Autodesk Fusion 360 part; units mm, degrees
(part 4 of 6)
component "611205 AIR - SOFFIT TOP RAIL - DOOR SIDE" placed x (1, 0, 0) y (0, 1, 0) z (0, 0, 1) at (0, 0, 0) in component "610201 AIR - SOFFIT"
component "611209 AIR - SOFFIT TOP RAIL - ROOM SIDE" placed x (1, 0, 0) y (0, 1, 0) z (0, 0, 1) at (0, 0, 0) in component "610201 AIR - SOFFIT"
component "611210 AIR - SOFFIT DOOR-SIDE PLATE" placed x (1, 0, 0) y (0, 1, 0) z (0, 0, 1) at (0, 0, 0) in component "610201 AIR - SOFFIT"
component "611206 AIR - SOFFIT END PLATE - LEFT" placed x (1, 0, 0) y (0, 1, 0) z (0, 0, 1) at (0, 0, 0) in component "610201 AIR - SOFFIT"
component "611203 AIR - SOFFIT FILL" placed x (1, 0, 0) y (0, 1, 0) z (0, 0, 1) at (0, 0, 0) in component "610201 AIR - SOFFIT"
component "611211 AIR - SOFFIT FILL - FRONT" placed x (1, 0, 0) y (0, 1, 0) z (0, 0, 1) at (0, 0, 0) in component "610201 AIR - SOFFIT"
component "611204 AIR - EXHAUST GRILLE" placed x (1, 0, 0) y (0, 1, 0) z (0, 0, 1) at (0, 0, 0) in component "610201 AIR - SOFFIT"
component "838001 HARDWARE - SOCKET HEAD BOLT - M6 X 16 - ISO 4762 8.8 ZINC" placed x (1, 0, 0) y (0, 1, 0) z (0, 0, 1) at (-588, -640, 2340.24) in component "610201 AIR - SOFFIT"
component "838001 HARDWARE - SOCKET HEAD BOLT - M6 X 16 - ISO 4762 8.8 ZINC" placed x (1, 0, 0) y (0, 1, 0) z (0, 0, 1) at (-588, -296, 2340.24) in component "610201 AIR - SOFFIT"
component "838001 HARDWARE - SOCKET HEAD BOLT - M6 X 16 - ISO 4762 8.8 ZINC" placed x (1, 0, 0) y (0, 1, 0) z (0, 0, 1) at (578, -640, 2340.24) in component "610201 AIR - SOFFIT"
component "838001 HARDWARE - SOCKET HEAD BOLT - M6 X 16 - ISO 4762 8.8 ZINC" placed x (1, 0, 0) y (0, 1, 0) z (0, 0, 1) at (578, -296, 2340.24) in component "610201 AIR - SOFFIT"
component "618105 AIR - SOFFIT UNDERSIDE HINGE - HOLD" placed x (1, 0, 0) y (0, 1, 0) z (0, 0, 1) at (-901, -641.14, 2132) in component "610201 AIR - SOFFIT"
component "618105 AIR - SOFFIT UNDERSIDE HINGE - HOLD" placed x (1, 0, 0) y (0, 1, 0) z (0, 0, 1) at (-321, -641.14, 2132) in component "610201 AIR - SOFFIT"
component "618105 AIR - SOFFIT UNDERSIDE HINGE - HOLD" placed x (1, 0, 0) y (0, 1, 0) z (0, 0, 1) at (207.75, -641.14, 2132) in component "610201 AIR - SOFFIT"
component "618105 AIR - SOFFIT UNDERSIDE HINGE - HOLD" placed x (1, 0, 0) y (0, 1, 0) z (0, 0, 1) at (681.25, -641.14, 2132) in component "610201 AIR - SOFFIT"
component "618106 AIR - SOFFIT UNDERSIDE LATCH - HOLD" placed x (1, 0, 0) y (0, 1, 0) z (0, 0, 1) at (-886, -305, 2132) in component "610201 AIR - SOFFIT"
component "618106 AIR - SOFFIT UNDERSIDE LATCH - HOLD" placed x (1, 0, 0) y (0, 1, 0) z (0, 0, 1) at (-306, -305, 2132) in component "610201 AIR - SOFFIT"
component "618106 AIR - SOFFIT UNDERSIDE LATCH - HOLD" placed x (1, 0, 0) y (0, 1, 0) z (0, 0, 1) at (222.75, -305, 2132) in component "610201 AIR - SOFFIT"
component "618106 AIR - SOFFIT UNDERSIDE LATCH - HOLD" placed x (1, 0, 0) y (0, 1, 0) z (0, 0, 1) at (696.25, -305, 2132) in component "610201 AIR - SOFFIT"
component "838002 HARDWARE - SOCKET HEAD BOLT - M6 X 25 - ISO 4762 8.8 ZINC" placed x (1, 0, 0) y (0, 1, 0) z (0, 0, 1) at (-1105, -296, 2340.24) in component "610201 AIR - SOFFIT"
component "838002 HARDWARE - SOCKET HEAD BOLT - M6 X 25 - ISO 4762 8.8 ZINC" placed x (1, 0, 0) y (0, 1, 0) z (0, 0, 1) at (-955, -296, 2340.24) in component "610201 AIR - SOFFIT"
component "610301 AIR - SPLITTER CARTRIDGE - COMMON (EXHAUST)" placed x (1, 0, 0) y (0, 1, 0) z (0, 0, 1) at (0, 0, 0) in component "610201 AIR - SOFFIT"
component "610402 AIR - EXHAUST FAN BOX" placed x (1, 0, 0) y (0, 1, 0) z (0, 0, 1) at (0, 0, 0) in component "610201 AIR - SOFFIT"
component "611301 AIR - CARTRIDGE CASING (1)" placed x (1, 0, 0) y (0, 1, 0) z (0, 0, 1) at (0, 0, 0) in component "610301 AIR - SPLITTER CARTRIDGE - COMMON (EXHAUST)"
component "611302 AIR - CARTRIDGE FILL - LAYER 50 (1)" placed x (1, 0, 0) y (0, 1, 0) z (0, 0, 1) at (-883, -634.14, 2161) in component "610301 AIR - SPLITTER CARTRIDGE - COMMON (EXHAUST)"
component "611302 AIR - CARTRIDGE FILL - LAYER 50 (1)" placed x (1, 0, 0) y (0, 1, 0) z (0, 0, 1) at (-883, -504.14, 2161) in component "610301 AIR - SPLITTER CARTRIDGE - COMMON (EXHAUST)"
component "611302 AIR - CARTRIDGE FILL - LAYER 50 (1)" placed x (1, 0, 0) y (0, 1, 0) z (0, 0, 1) at (-883, -374.14, 2161) in component "610301 AIR - SPLITTER CARTRIDGE - COMMON (EXHAUST)"
component "611401 AIR - FAN BOX CASING - EXHAUST" placed x (1, 0, 0) y (0, 1, 0) z (0, 0, 1) at (0, 0, 0) in component "610402 AIR - EXHAUST FAN BOX"
component "611403 AIR - FAN BOX BULKHEAD - EXHAUST" placed x (1, 0, 0) y (0, 1, 0) z (0, 0, 1) at (0, 0, 0) in component "610402 AIR - EXHAUST FAN BOX"
component "611405 AIR - FAN BOX LINING - EXHAUST SIDE" placed x (1, 0, 0) y (0, 1, 0) z (0, 0, 1) at (867, -633.14, 2162) in component "610402 AIR - EXHAUST FAN BOX"
component "611405 AIR - FAN BOX LINING - EXHAUST SIDE" placed x (1, 0, 0) y (0, 1, 0) z (0, 0, 1) at (867, -375.14, 2162) in component "610402 AIR - EXHAUST FAN BOX"
component "611406 AIR - FAN BOX LINING - EXHAUST FAR END" placed x (1, 0, 0) y (0, 1, 0) z (0, 0, 1) at (0, 0, 0) in component "610402 AIR - EXHAUST FAN BOX"
component "618401 AIR - FAN - NOCTUA NF-A14 INDUSTRIALPPC-3000 PWM" placed x (1, 0, 0) y (0, 1, 0) z (0, 0, 1) at (939.75, -479.14, 2305) in component "610402 AIR - EXHAUST FAN BOX"
component "618401 AIR - FAN - NOCTUA NF-A14 INDUSTRIALPPC-3000 PWM" placed x (1, 0, 0) y (0, 1, 0) z (0, 0, 1) at (1085.25, -479.14, 2305) in component "610402 AIR - EXHAUST FAN BOX"
component "611402 AIR - FAN BOX CASING - SUPPLY" placed x (1, 0, 0) y (0, 1, 0) z (0, 0, 1) at (0, 0, 0) in component "610401 AIR - SUPPLY FAN BOX"
component "611404 AIR - FAN BOX BULKHEAD - SUPPLY" placed x (1, 0, 0) y (0, 1, 0) z (0, 0, 1) at (0, 0, 0) in component "610401 AIR - SUPPLY FAN BOX"
component "611407 AIR - FAN BOX LINING - SUPPLY END" placed x (1, 0, 0) y (0, 1, 0) z (0, 0, 1) at (683, -816, 1795) in component "610401 AIR - SUPPLY FAN BOX"
component "611407 AIR - FAN BOX LINING - SUPPLY END" placed x (1, 0, 0) y (0, 1, 0) z (0, 0, 1) at (927, -816, 1795) in component "610401 AIR - SUPPLY FAN BOX"
component "611408 AIR - FAN BOX LIP ANGLE - SUPPLY" placed x (1, 0, 0) y (0, 1, 0) z (0, 0, 1) at (0, 0, 0) in component "610401 AIR - SUPPLY FAN BOX"
component "618402 AIR - FAN BOX PAD - SUPPLY - RUBBER 40 X 15 X 5 - HOLD" placed x (1, 0, 0) y (0, 1, 0) z (0, 0, 1) at (685, -841.5, 1650) in component "610401 AIR - SUPPLY FAN BOX"
component "618402 AIR - FAN BOX PAD - SUPPLY - RUBBER 40 X 15 X 5 - HOLD" placed x (1, 0, 0) y (0, 1, 0) z (0, 0, 1) at (979.7, -841.5, 1650) in component "610401 AIR - SUPPLY FAN BOX"
component "618501 AIR - RISER BUFFER - RUBBER - M6 - HOLD" placed x (1, 0, 0) y (0, 1, 0) z (0, 0, 1) at (0, 0, 0) in component "610401 AIR - SUPPLY FAN BOX"
component "618401 AIR - FAN - NOCTUA NF-A14 INDUSTRIALPPC-3000 PWM" placed x (1, 0, 0) y (0, 1, 0) z (0, 0, 1) at (756.5, -741.5, 1700) in component "610401 AIR - SUPPLY FAN BOX"
component "618401 AIR - FAN - NOCTUA NF-A14 INDUSTRIALPPC-3000 PWM" placed x (1, 0, 0) y (0, 1, 0) z (0, 0, 1) at (903.5, -741.5, 1700) in component "610401 AIR - SUPPLY FAN BOX"
component "618102 AIR - SUPPLY TRANSITION - HOLD" placed x (1, 0, 0) y (0, 1, 0) z (0, 0, 1) at (0, 0, 0) in component "610401 AIR - SUPPLY FAN BOX"
component "611501 AIR - INTAKE RISER" placed x (1, 0, 0) y (0, 1, 0) z (0, 0, 1) at (0, 0, 0) in component "610401 AIR - SUPPLY FAN BOX"
component "618103 AIR - RISER TRANSITION - HOLD" placed x (1, 0, 0) y (0, 1, 0) z (0, 0, 1) at (0, 0, 0) in component "610401 AIR - SUPPLY FAN BOX"
equation "pod_w = 2500 mm" comment "DECIDED: skeleton P04: D-01; conventions s4 (X = +-1250)"
equation "pod_d = 1700 mm" comment "DECIDED: skeleton P04: D-01; conventions s4 (Y = +-850)"
equation "pod_h = 2400 mm" comment "DECIDED: skeleton P04: D-21 (room floor to roof skin top)"
equation "glide_h = 10 mm" comment "ASSUMPTION: skeleton P04: layout study inputs.py glide_h"
equation "band_h = 100 mm" comment "SOURCE: skeleton P04: layout study B1 list B-BAND 100x40; inputs.py base_h"
equation "band_t = 40 mm" comment "SOURCE: skeleton P04: layout study B1 list B-BAND 100x40"
equation "skin_t = 3 mm" comment "DECIDED: skeleton P04: ACP skin, walls and ceiling (D-16; PM ruling 2026-10-31 on outer_t)"
equation "bond_t = 3 mm" comment "DECIDED: skeleton P04: bond line between the ACP and the frame (PM ruling 2026-10-31 on outer_t)"
equation "frame_t = 40 mm" comment "DECIDED: skeleton P04: aluminium frame tube depth, walls and ceiling (PM ruling 2026-10-31 on outer_t)"
equation "outer_t = skin_t + bond_t + frame_t" comment "DECIDED: skeleton P04: PM ruling 2026-10-31: ACP 3 + bond line 3 + frame 40, walls and ceiling (was 43)"
equation "cav_gap = 4 mm" comment "DECIDED: skeleton P04: D-16, D-42: the gap between the outer panel and the lining cassette in the wall and ceiling stack"
equation "cass_t = 34 mm" comment "SOURCE: skeleton P04: layout study B1 final list L-CASS 34 (tray + 25 gap + felt 9)"
equation "stack_t = outer_t + cav_gap + cass_t" comment "CALCULATION: skeleton P04: D-16, D-42 stack, walls and ceiling: outer panel + cavity gap + cassette (PM ruling 2026-10-31 on outer_t)"
equation "wall_depth = 1495 mm" comment "DECIDED: skeleton P04: PM ruling pass C: side walls start at the decor back plate (Y -645), as v1 (1496)"
equation "lin_gap = 4 mm" comment "ASSUMPTION: skeleton P04: PM ruling pass C: gap above the upper side linings so they stay floating (= the 4 mm stack gap)"
equation "seam_gap = 2.26 mm" comment "DECIDED: skeleton P04: PM ruling 2026-10-31 (Mechanical Checker F-001, F-005): the Joints Engineer's 2.26 mm at all nine site seam types, set by a metal stop (1.5 stop washer + 0.76 rivnut head; joints register section 2.8)"
equation "mat_t = 0 mm" comment "DECIDED: skeleton P04: D-132 (PM ruling 2026-11-01): no floor, so no floor mat (was 3, D-72)"
equation "floor_t = 0 mm" comment "DECIDED: skeleton P04: D-132 (PM ruling 2026-11-01): no floor; people stand on the room floor (was 9)"
equation "thresh_h = 0 mm" comment "DECIDED: skeleton P04: D-132 (PM ruling 2026-11-01): no threshold, no step at the door; the door's drop seal closes on the room floor (was 13)"
equation "decor_d = 205 mm" comment "SOURCE: skeleton P04: v1 geometry per the PM ruling on D-39 (as v1; the drawings win): v1 decor-frame drawing frames 191 (left) and 197 (right) deep plus ACP and back plate = the v1 STEP shell, Y -850 to -645 = 205. D-39 and the B1 list say 230-235 (v1 BOM); see BUILD-RECORD-P02"
equation "dl_w = 278 mm" comment "SOURCE: skeleton P04: B1 list F-DL 278 (v1 BOM DL)"
equation "dr_w = 1016 mm" comment "SOURCE: skeleton P04: B1 list F-DR 1016 (v1 STEP solid 78)"
equation "dt_w = 1697 mm" comment "SOURCE: skeleton P04: B1 list F-DT 1697 (v1 BOM DT)"
equation "dt_h = 280 mm" comment "SOURCE: skeleton P04: B1 list F-DT 280"
equation "door_w = 1176 mm" comment "DECIDED: skeleton P04: D-46"
equation "door_h = 2011 mm" comment "SOURCE: skeleton P04: B1 list F-GLASS-DOOR 2011; v1 STEP solid 238"
equation "glass_t = 8.76 mm" comment "DECIDED: skeleton P04: D-46 (4+4 laminate)"
equation "glass_y = 699 mm" comment "SOURCE: skeleton P04: v1 STEP solid 238 centre Y = -699 (layout study data)"
equation "kick_d = 20 mm" comment "ASSUMPTION: skeleton P04: kick strip envelope depth (D-40 gives the height only)"
equation "kick_gap = 7 mm" comment "SOURCE: skeleton P04: FRONT door unit: 7 mm running gap under the kick strip for the drop seal (Mechanical Checker F-002 on P03); since D-132 the PM puts the kick strip's bottom on the band's bottom line, glide_h, so the skeleton's kick envelope no longer uses it"
equation "fr_dz = 17 mm" comment "CALCULATION: skeleton P04: v1 front top 2417 (v2 frame) - pod_h 2400"
equation "door_xl = 289 mm" comment "SOURCE: skeleton P04: V1-FRONT-FACETS: door left edge X -961 = -1250 + 289"
equation "door_xbr = 1464 mm" comment "SOURCE: skeleton P04: V1-FRONT-FACETS: door bottom-right X 214"
equation "door_xtr = 1182 mm" comment "SOURCE: skeleton P04: V1-FRONT-FACETS: door top-right X -68"
equation "door_zb = 122 mm - fr_dz" comment "SOURCE: skeleton P04: V1-FRONT-FACETS: door bottom Z 122"
equation "door_zt = 2133 mm - fr_dz" comment "SOURCE: skeleton P04: V1-FRONT-FACETS: door top Z 2133"
equation "glass_gap = 4 mm" comment "DECIDED: skeleton P04: PM ruling 2026-10-31 on Mechanical Checker F-014: the fixed glass's free edge runs parallel to the door's slanted edge, 4.0 mm away (FRONT's glass in PR #28 is the reference)"
equation "fix_xbr = 302 mm" comment "SOURCE: skeleton P04: V1-FRONT-FACETS: fixed glass bottom-right X 948 = 1250 - 302"
equation "fix_xk = 501 mm" comment "SOURCE: skeleton P04: V1-FRONT-FACETS: fixed glass knee X 749 = 1250 - 501"
equation "fix_zk = 1538 mm - fr_dz" comment "SOURCE: skeleton P04: V1-FRONT-FACETS: fixed glass knee Z 1538"
equation "fix_xtr = 1480 mm" comment "SOURCE: skeleton P04: V1-FRONT-FACETS: fixed glass top-right X 230 = -1250 + 1480"
equation "fix_zb = 119 mm - fr_dz" comment "SOURCE: skeleton P04: V1-FRONT-FACETS: fixed glass bottom Z 119"
equation "fix_zt = 2136 mm - fr_dz" comment "SOURCE: skeleton P04: V1-FRONT-FACETS: fixed glass top Z 2136"
equation "dt_zb = 2137 mm - fr_dz" comment "SOURCE: skeleton P04: V1-FRONT-FACETS: DT and DR edge above the glass Z 2137"
equation "ch_zlo = 2217 mm - fr_dz" comment "SOURCE: skeleton P04: V1-FRONT-FACETS: top chamfer front edge Z 2217 at Y -848"
equation "ch_yb = 672 mm" comment "SOURCE: skeleton P04: V1-FRONT-FACETS: top chamfer back edge Y -672"
equation "dl_x2 = 92 mm" comment "SOURCE: skeleton P04: V1-FRONT-FACETS: DL facet knee X -1158 = -1250 + 92"
equation "dl_y2 = 752 mm" comment "SOURCE: skeleton P04: V1-FRONT-FACETS: DL facet knee Y -752"
equation "dl_x3 = 271 mm" comment "SOURCE: skeleton P04: V1-FRONT-FACETS: DL front corner X -979"
equation "dl_y3 = 844 mm" comment "SOURCE: skeleton P04: V1-FRONT-FACETS: DL front corner Y -844"
equation "dl_y1 = 670 mm" comment "SOURCE: skeleton P04: V1-FRONT-FACETS: DL outer facet start Y -670"
equation "dl_zo = 2414 mm - fr_dz" comment "SOURCE: skeleton P04: V1-FRONT-FACETS: DL top at the outer corner Z 2414"
equation "dt_x2 = 281 mm" comment "SOURCE: skeleton P04: V1-FRONT-FACETS: DT lower facet left X -969 = -1250 + 281"
equation "dt_y2 = 767 mm" comment "SOURCE: skeleton P04: V1-FRONT-FACETS: DT lower facet left Y -767"
equation "dt_y3 = 753 mm" comment "SOURCE: skeleton P04: V1-FRONT-FACETS: DT lower facet outer Y -753 at X -1154"
equation "dr_xc = 198 mm" comment "SOURCE: skeleton P04: V1-FRONT-FACETS: DR corner facet front X 1052 = 1250 - 198"
equation "dt_xr = 1699 mm" comment "SOURCE: skeleton P04: V1-FRONT-FACETS: DT/DR joint at the top, X 449 = -1250 + 1699 (PM ruling pass C)"
equation "dr_yc = 672 mm" comment "SOURCE: skeleton P04: V1-FRONT-FACETS: DR corner facet back Y -672"
equation "fix_xbl = door_xbr + ( door_zb - fix_zb ) * ( door_xbr - door_xtr ) / ( door_zt - door_zb ) + glass_gap * sqrt(( door_xbr - door_xtr ) * ( door_xbr - door_xtr ) + ( door_zt - door_zb ) * ( door_zt - door_zb )) / ( door_zt - door_zb )" comment "CALCULATION: skeleton P04: F-014: fixed glass bottom-left, on the line glass_gap from the door's slanted edge (was v1's 1468)"
equation "fix_xtl = door_xbr + ( door_zb - fix_zt ) * ( door_xbr - door_xtr ) / ( door_zt - door_zb ) + glass_gap * sqrt(( door_xbr - door_xtr ) * ( door_xbr - door_xtr ) + ( door_zt - door_zb ) * ( door_zt - door_zb )) / ( door_zt - door_zb )" comment "CALCULATION: skeleton P04: F-014: fixed glass top-left, on the same line (was v1's 1184)"
equation "floor_top = mat_t + floor_t" comment "CALCULATION: skeleton P04: the floor top: Z 0, the room floor itself (D-132: no floor; was Z 12)"
equation "wall_z0 = glide_h + band_h" comment "CALCULATION: skeleton P04: base band top: glides + band"
equation "panel_z0 = wall_z0 + seam_gap" comment "CALCULATION: skeleton P04: walls stand one seam_gap above the band top (joints register 2.8, IF-01)"
equation "wall_h = pod_h - wall_z0" comment "CALCULATION: skeleton P04: 2290 = layout study v2_model wall_h"
equation "side_h = ( wall_h - 2 * seam_gap ) / 2" comment "CALCULATION: skeleton P04: D-23: 2 sheets per side wall; the gap on the band and the horizontal seam (joints register 2.8)"
equation "side_l = wall_depth - seam_gap" comment "CALCULATION: skeleton P04: side panel length along Y: the seam_gap at the decor's back plate (joints register 2.8, IF-07)"
equation "back_oh = pod_h - outer_t - seam_gap - panel_z0" comment "CALCULATION: skeleton P04: PM ruling 2026-10-31 (pass D, F-004): the back outer frames run up to the ceiling frame (pod_h - outer_t), less the seam_gap under it, closing the slot at the back top edge"
equation "back_ph = ( back_oh - seam_gap ) / 2" comment "CALCULATION: skeleton P04: D-23: 4 sheets on the back, two equal rows with one seam_gap between them (joints register 2.8); the lower back linings match the lower row, as on the side walls"
equation "half_pw = ( pod_w - 2 * outer_t - 3 * seam_gap ) / 2" comment "CALCULATION: skeleton P04: SKIN width of each back and ceiling panel: two skins and three seam_gap seams between the side frames (F-001, joints register 2.8)"
equation "close_gap = 5.5 mm" comment "DECIDED: skeleton P04: PM ruling 2026-10-31 (joints register, F-011/F-012): frame gap at the closing seams B1-B2, B3-B4 and C1-C2, which have no hard stop (slotted holes, thicker gasket)"
equation "half_fw = ( pod_w - 2 * outer_t - 2 * seam_gap - close_gap ) / 2" comment "CALCULATION: skeleton P04: FRAME width of each back and ceiling panel: the skins overhang their frames by half_pw - half_fw at the closing seam (PM ruling 2026-10-31)"
equation "inner_w = pod_w - 2 * stack_t" comment "CALCULATION: skeleton P04: inside width between the side linings"
equation "bolt_edge_inset = 220 mm" comment "DECIDED: skeleton P04: PM ruling 2026-10-31: on every bolted edge the end bolts sit this far in from each panel end (the FRAME end, where the bolts go), the rest evenly spaced"
equation "spigot_inset = 100 mm" comment "DECIDED: skeleton P04: PM ruling 2026-10-31: locating spigots this far in from each panel end (round hole at one end, slot at the other)"
equation "base_bolt_edge = bolt_edge_inset" comment "DECIDED: skeleton P04: J-BASE-01 wall to band: the edge rule (kept by this name for parts already linked)"
equation "n_base_bolt = 4" comment "DECIDED: skeleton P04: PM ruling 2026-10-31, J-BASE-01: bolts per panel along the band, evenly spaced"
equation "base_spigot_inset = spigot_inset" comment "DECIDED: skeleton P04: J-BASE-01: the spigot rule (kept by this name for parts already linked)"
equation "base_side_y0 = pod_d / 2 - wall_depth + seam_gap" comment "CALCULATION: skeleton P04: J-BASE-01: side bolt lines start at the side panel's front end (first bolt base_bolt_edge further on)"
equation "side_base_pitch = ( side_l - 2 * base_bolt_edge ) / ( n_base_bolt - 1 )" comment "CALCULATION: skeleton P04: J-BASE-01 bolt pitch along a side panel"
equation "base_back_x0 = pod_w / 2 - outer_t - seam_gap" comment "CALCULATION: skeleton P04: J-BASE-01: back bolt lines start at each back FRAME's outer end, X -/+ this (first bolt base_bolt_edge further in)"
equation "back_base_pitch = ( half_fw - 2 * base_bolt_edge ) / ( n_base_bolt - 1 )" comment "DECIDED: skeleton P04: PM ruling 2026-10-31 (Reviewer 5 P2 on #58): J-BASE-01 pitch along a back panel, measured on the FRAME (half_fw), where the bolts go; 'panel end' means the frame end"
equation "ceil_bolt_z = pod_h - outer_t + frame_t / 2" comment "DECIDED: skeleton P04: PM ruling 2026-10-31, J-CEIL-01 wall to ceiling: the bolt line on the ceiling frame's centre (Z 2374)"
equation "n_ceil_side_bolt = 4" comment "DECIDED: skeleton P04: PM ruling 2026-10-31, J-CEIL-01: bolts along each side wall top"
equation "n_ceil_back_bolt = 4" comment "DECIDED: skeleton P04: PM ruling 2026-10-31, J-CEIL-01: bolts along each back panel top, like the base (pitch about 253, every edge 350 or less; joints register: 82 bolts in all)"
equation "ceil_side_y0 = pod_d / 2 - wall_depth" comment "DECIDED: skeleton P04: PM ruling 2026-10-31 (joints register): J-CEIL-01 side bolt lines start at Y -645, measured along the ceiling (first bolt bolt_edge_inset further on)"
equation "ceil_side_pitch = ( wall_depth - 2 * bolt_edge_inset ) / ( n_ceil_side_bolt - 1 )" comment "DECIDED: skeleton P04: PM ruling 2026-10-31 (joints register): J-CEIL-01 pitch along a side wall top, over the ceiling's length (was over the side panel's)"
equation "ceil_back_x0 = pod_w / 2 - outer_t - seam_gap" comment "DECIDED: skeleton P04: PM ruling 2026-10-31 (joints register): J-CEIL-01 back bolt lines start at each back frame's outer end, X -/+ this"
equation "ceil_back_pitch = ( half_fw - 2 * bolt_edge_inset ) / ( n_ceil_back_bolt - 1 )" comment "DECIDED: skeleton P04: PM ruling 2026-10-31 (joints register): J-CEIL-01 pitch along a back panel top, on the frame (half_fw)"
equation "tube_w = 20 mm" comment "CONFIRMED: D-34, D-54: aluminium 20 x 40 x 1.2 members (the 20 mm face lies in the plane of the panel)"
equation "tube_t = 1.2 mm" comment "CONFIRMED: D-54: the frames stay 1.2 mm (rivnut grip check passed); D-85 keeps the ceiling's cross members at 1.2 too, since they carry the overhead clips and catches (T07, T08 test on 1.2)"
equation "back_w = 40 mm" comment "CONFIRMED: R-J3 (joints register 2.4): the ceiling's back member is 40 x 40, so the back panel's top tube overlaps it by 34 and its rivnuts sit on a 40 mm face"
equation "fr_n = 3" comment "CONFIRMED: PM ruling on the CEILING plan, 2026-10-31: 3 cross members between the side and seam members"
equation "fr_pitch = ( wall_depth - tube_w ) / ( fr_n + 1 )" comment "CALCULATION: centre spacing of the cross members, front member to back member: (1495 - 20) / 4 = 368.75, 400 or less (D-16)"
equation "hole_clr = 7 mm" comment "CONFIRMED: R-J6 (joints register 2.9): bolt clearance hole, positioned to +/-0.2 from the spigot hole"
equation "hole_acc = 19 mm" comment "CONFIRMED: joints register 2.2, 2.9: access hole, so the 18 mm head washer goes in with the bolt"
equation "hole_rvn = 10.0 mm" comment "SOURCE: D-163 (pod-wide ruling 2026-11-01): the M6 rivnut 838003 is Sherex CAL2-610-4.2, the knurled round body, in a round drilled hole Ø10.00 +0.10 (was CAH2's Ø9.53; T06's spin-out test, 4 N·m or more in the real tubes, confirms it; the joints register's H-03)"
equation "spig_hole = 8.5 mm" comment "CONFIRMED: R-J13: spigot hole 8.5, round at one end of the edge, an 8.5 x 14 slot along it at the other"
equation "spig_slot = 14 mm" comment "CONFIRMED: R-J13: the spigot slot's length along the edge (+/-2.75 of travel for the 8 mm spigot)"
equation "lead_in = 1 mm" comment "CONFIRMED: R-J9 (joints register 2.10): 1 x 45 deg lead-in on the lower edges of the C1-C2 faces, so C2 drops past C1 without catching the seal"
equation "cj_back_y = pod_d / 2 - outer_t + frame_t / 2" comment "CONFIRMED: R-J15 (joints register 2.4): the back edges' bolt line on the back panel's top tube centre (Y +824)"
equation "cj_pin_n = 4" comment "CONFIRMED: J-CEIL-02 (joints register 3.6): 4 pins at the 220 mm rule along the C1-C2 seam"
equation "cj_pin_pitch = ( wall_depth - 2 * bolt_edge_inset ) / ( cj_pin_n - 1 )" comment "CALCULATION: J-CEIL-02 pins along the ceiling's 1495 from Y -645 + 220, as the side edges (joints register 2.9)"
equation "cj_spig_x0 = close_gap / 2 + spigot_inset" comment "CALCULATION: R-J13: spigots 100 in from each frame end. The round hole sits at the centre-seam end, since ST-04 runs from the round hole to the closing face (+/-0.1); the slot at the side end lets the side bolts pull C1 and C2 onto their stops"
equation "cj_spig_x1 = close_gap / 2 + half_fw - spigot_inset" comment "CALCULATION: R-J13: the slot 100 in from the frame's side end"
equation "x1_ov = 16 mm" comment "CONFIRMED: PM ruling 2026-11-01 (D-87 hooks): cross member X1 sits this far over the soffit's back edge, so the soffit's back hangers have a member above them; its back face stays over the cassette for the clips"
equation "hang_x = inner_w / 4" comment "CALCULATION: PM ruling 2026-11-01: soffit keyhole studs at the middle of each ceiling half's front member and X1 (clear of the clips, the catches and the roof slot)"
equation "lock_x = inner_w / 2 - 66 mm" comment "ASSUMPTION: PM rulings 2026-11-01: two captive screws (5 mm key) lock the soffit, so taking a cassette out can never free it; in cross member 1 since DR's new panel face (the room-side rail's loaded edge 18 mm away), over the soffit's left inlet plenum where no cartridge is, reached through its left hinged underside; C2's cross member carries the mirrored rivnuts unused, so the member stays one part"
equation "lock_dx = 150 mm" comment "ASSUMPTION: spacing of the two soffit lock screws along cross member 1"
equation "slot_x0 = 872 mm" comment "SOURCE: air report 7e (sized on skeleton P04): roof slot X 872 to 1157, over the soffit's exhaust fan box"
equation "slot_w = 285 mm" comment "SOURCE: air report 7e: roof slot 285 x 294"
equation "slot_d = 294 mm" comment "SOURCE: air report 7e: roof slot 285 x 294"
equation "slot_y0 = -620 mm" comment "CONFIRMED: D-61, PM ruling 2026-10-31: roof slot Y -620 to -326, 5 mm clear of the frame's front member"
equation "cs_front = 360 mm" comment "CONFIRMED: D-60 soffit over the door head, 360 deep and 220 tall (Z 2120 to 2340), flush with the air column's face (PM rulings 2026-10-31, air group); the cassettes stop at its back face (PM ruling 2026-10-31)"
equation "cs_gap = 3 mm" comment "ASSUMPTION: edge gap round the cassette to the next lining, the other cassette or the top decor block; the 3.2 mm PORON gasket (selection D) just touches across it"
equation "cs_w = inner_w / 2 - 2 * cs_gap" comment "CALCULATION: cassette width: half the 2338 inside width less a gap each side = 1163"
equation "cs_d = wall_depth - stack_t - cs_front - 2 * cs_gap" comment "CALCULATION: cassette length front to back: the 1414 envelope (decor back plate to the back lining face) less the soffit and a gap each end = 1408 with no soffit"
equation "tray_t = 0.5 mm" comment "CONFIRMED: D-37: galvanised steel tray 0.5 mm (DX51D+Z, selection B)"
equation "tray_h = cass_t" comment "CALCULATION: PM ruling on the CEILING plan, 2026-10-31: the returns run the full cassette depth (34) and turn in under the felt edge"
equation "lip_w = 12 mm" comment "CONFIRMED: PM ruling on the CEILING plan, 2026-10-31: a 12 mm lip under the felt edge"
equation "bend_r = tray_t" comment "ASSUMPTION: inside bend radius 1 x t for 0.5 mm DX51D (the sheet metal rule's bend radius is its Thickness); the factory's tooling sets it (guideline 9)"
equation "felt_t = 9 mm" comment "CONFIRMED: D-17: 9 mm PET felt on the cassette face (plan VT03-PET)"
equation "felt_c = 1 mm" comment "ASSUMPTION: felt edge clearance inside the returns, so the felt drops onto the lips"
equation "gap_h = tray_h - felt_t - 2 * tray_t" comment "CALCULATION: air gap between the tray base and the felt (24): the cable path (D-41) and the acoustic gap (D-17)"
equation "rib_n = 2" comment "CONFIRMED: PM ruling on the CEILING plan, 2026-10-31: 2 ribs keep the felt flat"
equation "rib_off = cs_w / 6" comment "CALCULATION: rib centre from the cassette centre line: with 2 ribs the felt spans 3 equal widths of cs_w / 3 = 388"
equation "rib_crown = 20 mm" comment "ASSUMPTION: flat width of the rib that carries the felt"
equation "rib_fl = 12 mm" comment "ASSUMPTION: rib top flange width against the tray base; the rib-to-tray joint is HOLD"
equation "rib_end = 5 mm" comment "ASSUMPTION: clearance from each rib end to the returns"
equation "fill_t = 40 mm" comment "CONFIRMED: D-24: 40 mm PET fill rides on the cassette back (25 kg/m3 by default, PM ruling 2026-10-31)"
equation "fill_c = 5 mm" comment "ASSUMPTION: fill clearance to the frame members, clips and catches, so the cassette never touches the frame (D-17)"
equation "fill_min = 100 mm" comment "ASSUMPTION: a fill strip shorter than this isn't made (a bay mostly over the soffit)"
equation "fill_hw = inner_w / 4 - close_gap / 2 - tube_w - fill_c" comment "CALCULATION: half length of a fill strip, set by the seam member over the cassette's inner edge and used on both sides, so both cassettes stay the same part"
equation "clip_w = 40 mm" comment "ASSUMPTION: clip space along X; HOLD H03 / ISS-076 until a clip is named with its rating"
equation "clip_d = 30 mm" comment "ASSUMPTION: clip space out from the member face; HOLD H03 / ISS-076"
equation "clip_h = 30 mm" comment "ASSUMPTION: clip space above the tray; HOLD H03 / ISS-076"
equation "catch_w = 40 mm" comment "ASSUMPTION: safety catch space along X; HOLD H04 / ISS-076"
equation "catch_d = 30 mm" comment "ASSUMPTION: safety catch space out from the member face; HOLD H04 / ISS-076"
equation "catch_h = 40 mm" comment "ASSUMPTION: safety catch space above the tray, up the member face; HOLD H04 / ISS-076"
equation "cable_hole = 19.1 mm" comment "CONFIRMED: PM ruling 2026-11-01: the panel hole ELECTRICAL's cable bushing needs, in the front and back returns: the voice cockpit route from the back wall to the front (REQ-VCK-03, D-41) and the spare path (ISS-069)"
equation "sprk_d = 150 mm" comment "ASSUMPTION: reserved round zone for a later sprinkler drop (REQ-US-01)"
equation "col_gap = 5 mm" comment "CONFIRMED: PM ruling 2026-11-01 (BASE): the column keeps 5 mm off the floating side lining (D-17), X up to 1161; the soffit's ends the same"
equation "dr_back_t = 1.5 mm" comment "CONFIRMED: FRONT's DR model (dr_block.py), read at load: joints register J-FRONT-01: the back plate is aluminium 1.0 to 2.7 thick at each bolt, for the rivnuts (HOLD-10); 1.5, not 2, so DR stays under 20 kg (D-03; PM ruling 2026-11-01)"
equation "dr_acc_t = 3 mm" comment "CALCULATION: FRONT's DR model (dr_block.py), read at load: access panel 3 mm aluminium: it carries the air column's 10 kg on two hook studs 222 mm from its screwed edge (PM ruling 2026-11-01); 2 mm would see about 110 MPa if the column pulls 50 N, 3 mm about 50 MPa"
equation "dr_rn_head = 0.76 mm" comment "SOURCE: FRONT's DR model (dr_block.py), read at load: rivnut 838003 head 0.76 +/-0.08: Sherex CAL2-610-4.2 since D-163 (its own page: HT 0.76 +/-0.08, the same as the CAH2's), zinc-plated steel (D-131)"
equation "dr_stop_w = 1.6 mm" comment "SOURCE: FRONT's DR model (dr_block.py), read at load: an 838004 washer (ISO 7093 6.4 x 18, 1.6 thick) on each rivnut head: the panel's stop (Joints, D-130)"
equation "dr_pnl_gap = dr_rn_head + dr_stop_w" comment "CALCULATION: FRONT's DR model (dr_block.py), read at load: the inner face panel stands 2.36 off the frame on its stops; the 4.0 seal 848013 is squeezed to it (D-130)"
equation "dr_acc_face_y = -pod_d / 2 + decor_d - dr_back_t + dr_pnl_gap + dr_acc_t" comment "CALCULATION: FRONT's DR model (dr_block.py), read at load: named value for AIR (PM rulings 2026-11-01, D-130): the room-side face of DR's inner face panel, where AIR's air column and soffit start; Y -641.14, the 3 mm panel 2.36 off the frame on its stops"
equation "op_x0 = 961 mm" comment "SOURCE: FRONT's DR model (dr_block.py), read at load: air report 7f: the opening into the column from X 961"
equation "op_w = 185 mm" comment "SOURCE: FRONT's DR model (dr_block.py), read at load: the opening X 961 to 1146 (PM ruling 2026-11-01, from the AIR Transitions Engineer: the upper duct's gasket face and every metal edge keep 6 from the bolt-line tube and the band; it ran to the column's edge, 200 x 215)"
equation "op_z0 = 1895 mm" comment "SOURCE: FRONT's DR model (dr_block.py), read at load: D-60 air table: opening Z 1895 to 2102 (PM ruling 2026-11-01)"
equation "op_h = 207 mm" comment "SOURCE: FRONT's DR model (dr_block.py), read at load: Z 1895 to 2102 (PM ruling 2026-11-01, the AIR Transitions Engineer; was 215)"
equation "face_acp = 3 mm" comment "SOURCE: air report 7e (sized on skeleton P04): faces 3 mm ACP + 9 mm felt"
equation "face_felt = 9 mm" comment "SOURCE: air report 7e (sized on skeleton P04): faces 3 mm ACP + 9 mm felt"
equation "face_t = face_acp + face_felt" comment "CALCULATION: 12 mm felt-covered face"
equation "clr = 5 mm" comment "SOURCE: air report 7e (sized on skeleton P04): 5 mm round each cartridge and fan box, to slide it out"
equation "col_x0 = 949 mm" comment "SOURCE: air report 7e (sized on skeleton P04): the column's left face, X 949 (220 wide on P03, 217 on P04)"
equation "col_d = 360 mm" comment "CONFIRMED: D-61: the room face 360 from the side walls' front end (Y -285), flush with the soffit's face; the column itself starts at DR's access-panel face, so it is 358.5 deep"
equation "plen_lo = 120 mm" comment "SOURCE: air report 7e (sized on skeleton P04): the base plenum under the cartridge, 120 tall; now the least it may be, since the cartridge's foot follows FRONT's B01 screws (cart_b01_clr)"
equation "grille_h = 100 mm" comment "CONFIRMED: D-61: a 100 mm kick grille at the column's foot"
equation "grille_z = 10 mm" comment "SOURCE: air report 7e (sized on skeleton P04): kick grille Z 25 to 125, 10 mm above the column's foot"
equation "grille_l = 312 mm" comment "SOURCE: air report 7e (sized on skeleton P04): 529 along the front and left faces, 217 of it on the front"
equation "grille_t = 2 mm" comment "ASSUMPTION: perforated aluminium grille plates, flush with the room-side face; free area per the report, pattern HOLD"
equation "hub_w = 180 mm" comment "CONFIRMED: D-61, D-70: a 180 x 180 zone for the sensor hub and controls"
equation "hub_t = 29 mm" comment "SOURCE: air report 7e (sized on skeleton P04): up to 29 deep, no fill behind it"
equation "hub_z = 1200 mm" comment "SOURCE: air report 7e (sized on skeleton P04): zone centred at Z 1200; across, it is centred between the front corner angles (X 1063.5 on P04, the report's 1058 is the column's centre)"
equation "chase_w = 30 mm" comment "SOURCE: air report 7e (sized on skeleton P04): a 30 x 30 cable chase in the column's front-left corner"
equation "foot_t = 2 mm" comment "ASSUMPTION: column foot plate, aluminium; it closes the base plenum and takes BASE's two spigots"
equation "spg1_x = 989 mm" comment "CONFIRMED: PM ruling 2026-11-01: BASE's spigot S1 on F2 (X 989, Y -605), into a round hole"
equation "spg1_y = -605 mm" comment "CONFIRMED: PM ruling 2026-11-01: BASE's spigot S1 on F2"
equation "spg2_x = 1126 mm" comment "CONFIRMED: PM ruling 2026-11-01: BASE's spigot S2 on F2 (X 1126, Y -337), into a slot"
equation "spg2_y = -337 mm" comment "CONFIRMED: PM ruling 2026-11-01: BASE's spigot S2 on F2"
equation "spg_hole = 8.5 mm" comment "CONFIRMED: R-J13 rule for spigots: 8.5 round at one, 8.5 x 14 slot at the other (along Y here)"
equation "spg_slot = 14 mm" comment "CONFIRMED: R-J13: slot length"
equation "plate_t = 1 mm" comment "ASSUMPTION: aluminium plates closing the column's right side at the two plenums, now that the column stands 5 mm off the lining"
equation "hook_x = 971 mm" comment "CONFIRMED: PM ruling 2026-11-01: the column's two hook studs in DR's access panel at X 971 (FRONT's parts)"
equation "hook_z1 = 1700 mm" comment "CONFIRMED: PM ruling 2026-11-01: lower hook stud Z 1700"
equation "hook_z2 = 1850 mm" comment "CONFIRMED: PM ruling 2026-11-01: upper hook stud Z 1850"
equation "key_d = 12 mm" comment "ASSUMPTION: keyhole's big hole, for a 10 mm stud head"
equation "key_w = 6.5 mm" comment "ASSUMPTION: keyhole's slot and the rails' forks, for a 6 mm stud shank"
equation "key_drop = 10 mm" comment "CONFIRMED: PM ruling 2026-11-01: the column drops 10 mm onto its studs and BASE's spigots"
equation "ang_w = 20 mm" comment "ASSUMPTION: corner angle leg along the side faces; the report says 4 corner angles, size not given"
equation "ang_f = 9 mm" comment "ASSUMPTION: corner angle leg along the front face: short, so the 180 hub zone fits between the two front corners (212 - 12 - 2 x 9 = 182)"
equation "ang_t = 2 mm" comment "ASSUMPTION: corner angle thickness, aluminium"
equation "cart_w = 173 mm" comment "CONFIRMED: D-61: one cartridge 173 x 314 x 1750"
equation "cart_d = 314 mm" comment "CONFIRMED: D-61: one cartridge 173 x 314 x 1750"
equation "cart_l = 1750 mm" comment "CONFIRMED: D-61: one cartridge 173 x 314 x 1750"
equation "cart_t = 2 mm" comment "CONFIRMED: D-61: 2 mm aluminium casing; D-121 withdrew D-116's 1.8 mm, since the noise margin is gone"
equation "lay_t = 50 mm" comment "CONFIRMED: D-61: three 50 mm absorbent layers (Pyrotek Sorberpoly 2D at 32 kg/m3, report 7e; D-116)"
equation "pass_w = ( cart_d - 2 * cart_t - 3 * lay_t ) / 2" comment "CALCULATION: D-61: two 80 mm passages"
equation "sof_h = 220 mm" comment "CONFIRMED: D-61: soffit 220 tall, Z 2120 to 2340"
equation "eg_x0 = 16 mm" comment "SOURCE: air report 7e (sized on skeleton P04): exhaust grille from X -1150, 16 in from the soffit's left end"
equation "eg_l = 265 mm" comment "SOURCE: air report 7e (sized on skeleton P04): exhaust grille 265 x 336"
equation "eg_w = 336 mm" comment "SOURCE: air report 7e (sized on skeleton P04): exhaust grille 265 x 336"
equation "fb_w = 294 mm" comment "SOURCE: air report 7e (sized on skeleton P04): exhaust fans and box 294 x 314 x 173"
equation "sof_fill_t = 27 mm" comment "SOURCE: air report 7e (sized on skeleton P04): the exhaust cartridge sits on 27 mm of fill over the underside (Z 2159), as in the column"
equation "lin_t = 50 mm" comment "SOURCE: air report 7e (sized on skeleton P04): fan boxes lined with 50 mm"
equation "box_t = 2 mm" comment "SOURCE: air report 7e (sized on skeleton P04): 2 mm aluminium sheet, used for the soffit's left end plate"
equation "fbox_t = 3 mm" comment "CONFIRMED: D-124: both fan box casings in 3 mm aluminium (boost about 29.5 dB(A) at 65 l/s, 66.6 l/s reach, +1.4 kg; the fan sample decides)"
equation "rail_t = 3 mm" comment "ASSUMPTION: soffit top rails, aluminium flat bar, riveted to the door-side plate and the front face"
equation "dp_t = 2 mm" comment "ASSUMPTION: soffit door-side plate: carries the door-side rail, closes the soffit against DT's back plate and DR's back (DR's riveted band stays: PM ruling 2026-11-01)"
equation "rail_w = 24 mm" comment "ASSUMPTION: soffit top rail width (room side); the door-side rail runs from the soffit's door side to 24 from the side walls' front end (22.5 wide), so it stays 1 mm clear of the roof sleeve"
equation "stud_l = 16 mm" comment "CONFIRMED: D-90 (HOLD-18, joints register #99): the hanger studs are M6 x 16 socket head bolts"
equation "stud_eng = 9 mm" comment "ASSUMPTION: thread engaged in the ceiling's rivnut (10.16 installed length less the lead-in)"
equation "rvn_head = 0.76 mm" comment "SOURCE: H-03 rivnut head under the frame face (Sherex CAH2-610-4.2, 0.76, SHX2)"
equation "hd_h = 6 mm" comment "SOURCE: ISO 4762 M6 head height 6 (the studs and the lock screws)"
equation "hd_c = 1.5 mm" comment "CONFIRMED: D-90 (HOLD-18): 1.5 clear under each head"
equation "stud_d = 10 mm" comment "SOURCE: ISO 4762 M6 head diameter 10"
equation "slide = 24 mm" comment "CALCULATION: the soffit is lifted this far behind its place and slid toward the door: the studs start clear of both rails' edges"
equation "us_gap = 2 mm" comment "ASSUMPTION: gap between the underside sections"
equation "hinge_l = 60 mm" comment "ASSUMPTION: hinge envelope along the door-side edge, HOLD"
equation "latch_l = 30 mm" comment "ASSUMPTION: push latch envelope at the room-side edge, HOLD"
equation "hl_h = 8 mm" comment "ASSUMPTION: hinge and latch envelope height above the underside"
equation "fan_s = 140 mm" comment "SOURCE: Noctua NF-A14 industrialPPC-3000 PWM: 140 x 140 x 25 (selection F1)"
equation "fan_t = 25 mm" comment "SOURCE: Noctua NF-A14 industrialPPC-3000 PWM: 140 x 140 x 25 (selection F1)"
equation "lock_hole = 7.0 mm" comment "SOURCE: the joints register's R-J6: M6 bolt clearance holes 7.0 (the mechanical checks' C08 found 6.6 here, 0.31 mm of float over a rivnut)"
equation "fr_hd_d = 10 mm" comment "SOURCE: FRONT's DR rebuild (FRONT Engineer, 2026-11-01 07:57, with the Lead's correction: plain washers): M6 x 16 socket heads, ISO 4762, 10 across"
equation "fr_hd_h = 6 mm" comment "SOURCE: FRONT's DR rebuild (FRONT Engineer, 2026-11-01 07:57, with the Lead's correction: plain washers): M6 socket heads 6 high"
equation "fr_wsh_d = 12 mm" comment "SOURCE: FRONT's DR rebuild (FRONT Engineer, 2026-11-01 07:57, with the Lead's correction: plain washers): plain washers ISO 7089 M6, 12 across"
equation "fr_wsh_t = 1.6 mm" comment "SOURCE: FRONT's DR rebuild (FRONT Engineer, 2026-11-01 07:57, with the Lead's correction: plain washers): plain washers ISO 7089 M6, 1.6 thick (head and washer 7.6 proud)"
equation "fr_scr_clr = 1 mm" comment "ASSUMPTION: AIR's clearance round FRONT's screw heads and washers, and in each relief"
equation "b08_x1 = 499.0 mm" comment "SOURCE: FRONT's DR rebuild (FRONT Engineer, 2026-11-01 07:57, with the Lead's correction: plain washers): B08's first screw"
equation "b08_x2 = 821.7 mm" comment "SOURCE: FRONT's DR rebuild with D-137's 3 mm glue line (#313 at 541fe7f, FRONT Engineer, 2026-11-01 10:47): B08's second screw"
equation "b08_x3 = 1144.4 mm" comment "SOURCE: FRONT's DR rebuild with D-137's 3 mm glue line (#313 at 541fe7f, FRONT Engineer, 2026-11-01 10:47): B08's third screw"
equation "b08_z = 2140.1 mm" comment "SOURCE: FRONT's DR rebuild (FRONT Engineer, 2026-11-01 07:57, with the Lead's correction: plain washers): B08's three screws' height"
equation "b01_x1 = 1000.2 mm" comment "SOURCE: FRONT's DR rebuild with D-137's 3 mm glue line (#313 at 541fe7f, FRONT Engineer, 2026-11-01 10:47): B01's first screw, under the supply cartridge"
equation "b01_x2 = 1145.1 mm" comment "SOURCE: FRONT's DR rebuild with D-137's 3 mm glue line (#313 at 541fe7f, FRONT Engineer, 2026-11-01 10:47): B01's second screw, under the supply cartridge"
equation "b01_z = 130.0 mm" comment "SOURCE: FRONT's DR rebuild (FRONT Engineer, 2026-11-01 07:57, with the Lead's correction: plain washers): B01's two screws' height (washers to Z 136; the cartridge from Z 140)"
equation "cart_b01_clr = 4 mm" comment "CONFIRMED: the Lead's ruling 2026-11-01: the supply cartridge, lifted 6 (the Air Engineer's fix), stands 4 over the washers of B01's two screws; tied to them, so it holds when BASE's D-132 takes the floor out (floor top Z 12 to 0)"
equation "b07_x = 939.0 mm" comment "SOURCE: FRONT's DR rebuild (FRONT Engineer, 2026-11-01 07:57, with the Lead's correction: plain washers): B07's lowest screw, moved 4 clear of the column's left face"
equation "b07_z = 281.4 mm" comment "SOURCE: FRONT's DR rebuild with D-137's 3 mm glue line (#313 at 541fe7f, FRONT Engineer, 2026-11-01 10:47): B07's lowest screw's height (was 259.8)"
equation "blk_t = 2 mm" comment "SOURCE: the air report's sizing (calc.py, D-121): each fan box's 2 mm aluminium bulkhead, the fans mounted on it"
equation "fan_bore = 135 mm" comment "SOURCE: the air report's fan bore (calc.py FAN_BORE 0.135 m): the bulkhead's opening at each fan"
equation "fan_hp = 124.5 mm" comment "SOURCE: Noctua NF-A14 (140 mm frame): its 4 mounting holes on a 124.5 mm square (the maker's data sheet, selection F1)"
equation "fan_hole = 4.5 mm" comment "ASSUMPTION: clearance in the bulkhead for each fan screw into the fan's corner hole (the screw HOLD with the fan's mounting)"
equation "s_lin_gap = 70 mm" comment "SOURCE: D-121, the Air Engineer: the supply box's end-wall linings start about 70 mm above the fans, so the air reaches them"
equation "e_lin_gap = 50 mm" comment "SOURCE: D-121, the Air Engineer: the exhaust box's far-end lining stops 50 mm under the fans"
equation "sb_x0 = 680 mm" comment "SOURCE: PM ruling 2026-11-01 (the AIR Transitions Engineer's find, the Lead's ruling): the supply fan box X 680 to 980, 6.3 mm off DR's back ring diagonal tube B06 on FRONT's #313 STEP (at X 673, with the glue line and the box 3 mm back, it was 1.0) and 8.1 off the front ring's diagonal (FRONT's fan box points had X 673; report 7e X 645)"
equation "sb_w = 300 mm" comment "SOURCE: air report 7e (sized on skeleton P04): supply fan box 300 x 155 x 300"
equation "sb_d = 155 mm" comment "SOURCE: air report 7e (sized on skeleton P04): supply fan box 300 x 155 x 300"
equation "sb_h = 300 mm" comment "SOURCE: air report 7e (sized on skeleton P04): supply fan box 300 x 155 x 300"
equation "sb_yf = 31 mm" comment "SOURCE: PM ruling 2026-11-01 and FRONT's DR rebuild with D-137's 3 mm glue line (#313 at 541fe7f, FRONT Engineer, 2026-11-01 10:47): the supply fan box's front face at Y -819, 5 mm behind the cross tube F09 over it (Z 1904 to 1924), now 3 off the skin (was 28: Y -822)"
equation "sb_z0 = 1650 mm" comment "SOURCE: air report 7e (sized on skeleton P04): supply fan box Z 1650 to 1950"
equation "rs_x0 = 959 mm" comment "SOURCE: FRONT's DR rebuild with D-137's 3 mm glue line (#313 at 541fe7f, FRONT Engineer, 2026-11-01 10:47): the riser's space X 959 to 1098, 5.9 off the glass-edge tube B07 (was 956; report 7e had 955)"
equation "rs_w = 139 mm" comment "SOURCE: air report 7e (sized on skeleton P04): intake riser 139 wide, 155 deep"
equation "rs_d = 150 mm" comment "SOURCE: the air report's D-130 table (riser_y, riser_lo): the riser Y -803 to -653, 6.5 off DR's frame face (was 155; FRONT's ri_d follows with D-130). Its front-right edge runs 1.2 from DR's corner facet skin over its height, measured on #313's DR (the air report's 4.8 predates the 3 mm move right)"
equation "rs_y0 = -803 mm" comment "SOURCE: air report 7e (sized on skeleton P04): intake riser Y -803 to -648"
equation "rs_z0 = 252 mm" comment "SOURCE: FRONT's reserved space for the riser (DR model on main: its open foot 140 over DR's base, Z 252); D-130's sealed intake boot (611502, to come) takes the air from the mesh up to this foot (was Z 105)"
equation "rs_z1 = 1386 mm" comment "CONFIRMED: the Lead's ruling 2026-11-01 in the transitions group: the riser cut 60 shorter (was 1445, the air report's), so the lower duct's turn eases to 52 deg; the AIR Transitions Engineer's shape"
equation "rs_t = 1 mm" comment "CONFIRMED: D-61: 1 mm steel intake riser"
equation "rs_ch = 8 mm" comment "CONFIRMED: the Lead's ruling 2026-11-01: an 8 x 8 chamfer on the riser's front-right vertical edge, so it stands 6.5 from DR's corner facet skin instead of 1.2 (calculation on #313's DR STEP; the ruling said 6.8), for 0.15% of its area; the lower duct's bottom flange follows it (the AIR Transitions Engineer)"
equation "tr_rv_d = 4.1 mm" comment "SOURCE: the AIR Transitions Engineer's hole list 2026-11-01 (the transitions' flats carry the same holes): Ø4.1 for a Ø4.0 blind rivet until Joints picks the rivet (HOLD)"
equation "tr_col_in = 25 mm" comment "SOURCE: the AIR Transitions Engineer's hole list 2026-11-01 (the transitions' flats carry the same holes): the lower transition's collar slips 25 into the riser's top; its 10 rivets at the overlap's middle (Z 1373.5)"
equation "tr_rs_py = 50.5 mm" comment "SOURCE: the AIR Transitions Engineer's hole list 2026-11-01 (the transitions' flats carry the same holes): 3 rivets in each of the riser's side walls, 50.5 apart about its middle"
equation "tr_rs_x1 = 33.5 mm" comment "SOURCE: the AIR Transitions Engineer's hole list 2026-11-01 (the transitions' flats carry the same holes): the riser's front and back walls, the first rivet 33.5 from its left face (X 992.5)"
equation "tr_rs_x2 = 92.5 mm" comment "SOURCE: the AIR Transitions Engineer's hole list 2026-11-01 (the transitions' flats carry the same holes): the riser's front and back walls, the second rivet 92.5 from its left face (X 1051.5, clear of the chamfer)"
equation "tr_be_dz = 10 mm" comment "SOURCE: the AIR Transitions Engineer's hole list 2026-11-01 (the transitions' flats carry the same holes): 3 rivets in each of the box's end walls 10 above its bottom (Z 1660), through the lower transition's webs"
equation "tr_be_py = 50.5 mm" comment "SOURCE: the AIR Transitions Engineer's hole list 2026-11-01 (the transitions' flats carry the same holes): the box's end-wall rivets 50.5 apart about its middle"
equation "tr_bf_dz = 9 mm" comment "SOURCE: the AIR Transitions Engineer's hole list 2026-11-01 (the transitions' flats carry the same holes): 4 rivets in the box's front wall 9 below its top (Z 1941), into the upper transition's front"
equation "tr_bf_px = 164 mm / 3" comment "SOURCE: the AIR Transitions Engineer's hole list 2026-11-01 (the transitions' flats carry the same holes): the box's front-wall rivets X 748 to 912, even about its middle"
equation "tr_bb_dz = 58.5 mm" comment "SOURCE: the AIR Transitions Engineer's hole list 2026-11-01 (the transitions' flats carry the same holes): 4 rivets in the box's back wall 58.5 below its top (Z 1891.5), into the upper transition's back flange"
equation "tr_bb_x0 = 70.9 mm" comment "SOURCE: the AIR Transitions Engineer's hole list 2026-11-01 (the transitions' flats carry the same holes): the box's first back-wall rivet 70.9 from its left face (X 750.9)"
equation "tr_bb_px = 54.4 mm" comment "SOURCE: the AIR Transitions Engineer's hole list 2026-11-01 (the transitions' flats carry the same holes): the box's back-wall rivets 54.4 apart"
equation "dr_skin_t = 3 mm" comment "SOURCE: FRONT's DR skin, ACP 3 (DR model's dr_skin_t): DR's front ring tubes start behind it"
equation "dr_fr_w = 20 mm" comment "SOURCE: FRONT's DR frame tube 20 x 20 (DR model's fr_w): F07 and F08"
equation "dr_f08_x1 = 1029.7 mm" comment "SOURCE: FRONT's DR STEP on #313 (541fe7f, 350003 P01, every tube 3 off its skin): F08's and F07's right end, at the facet side tube F02's inner face"
equation "dr_f07_zc = 844 mm" comment "SOURCE: FRONT's DR STEP on #313 (541fe7f, 350003 P01, every tube 3 off its skin): F07, the front ring's cross tube, Z 834 to 854"